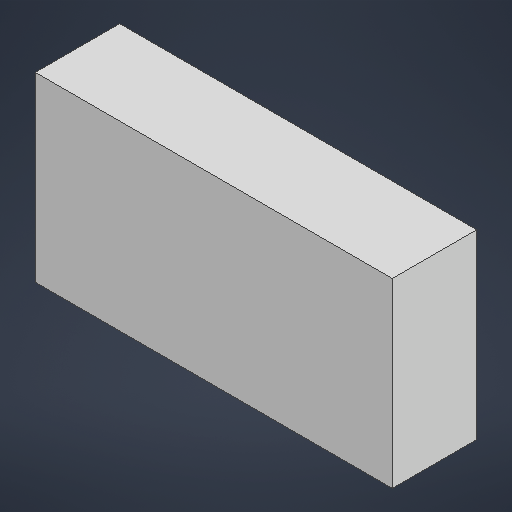
# Autodesk Inventor part: DUMMY-ESP32
Saved by Autodesk Inventor 2027.1 (Build 311270010, 270A)
## iProperties
Created: 2026-10-28
Part Number: DUMMY-ESP32
Material: Generic
Description: ESP32 DevKitC
Document SubType Name: Modeling
Designer: shyan
Density: 1 g/cm^3
Appearance: Default
Mass: 10 g
Author: shyan
Autodesk Inventor part; units mm, degrees
ref_plane "YZ Plane" through (0, 0, 0) normal (1, 0, 0) x (0, 1, 0)
ref_plane "XZ Plane" through (0, 0, 0) normal (0, 1, 0) x (-1, 0, 0)
ref_plane "XY Plane" through (0, 0, 0) normal (0, 0, 1) x (1, 0, 0)
sketch "sk_body" plane through (0, 0, 0) normal (0, 0, 1) x (1, 0, 0)
  line L0 (-27.5, -14) -> (27.5, -14)
  line L1 (27.5, -14) -> (27.5, 14)
  line L2 (27.5, 14) -> (-27.5, 14)
  line L3 (-27.5, 14) -> (-27.5, -14)
  line L4 (-38.5, 0) -> (38.5, 0) construction
  line L5 (0, -19.6) -> (0, 19.6) construction
  point P0 (0, 0)
  dimension "d0" = 55
  dimension "d1" = 28
  constraints: 8 end point, 2 parallel, 1 horizontal, 1 perpendicular, 2 other
  measures "d0" distance of L0.start L0.end
  measures "d1" distance of L0.end L1.end
extrude "Body" add sketch "sk_body" along normal blind 13
equation "\"d0\" = esp_W"
equation "\"d1\" = esp_D"
equation "\"d2\" = esp_H"
equation "\"esp_W\" = 55"
equation "\"esp_D\" = 28"
equation "\"esp_H\" = 13"
body "Solid1"
